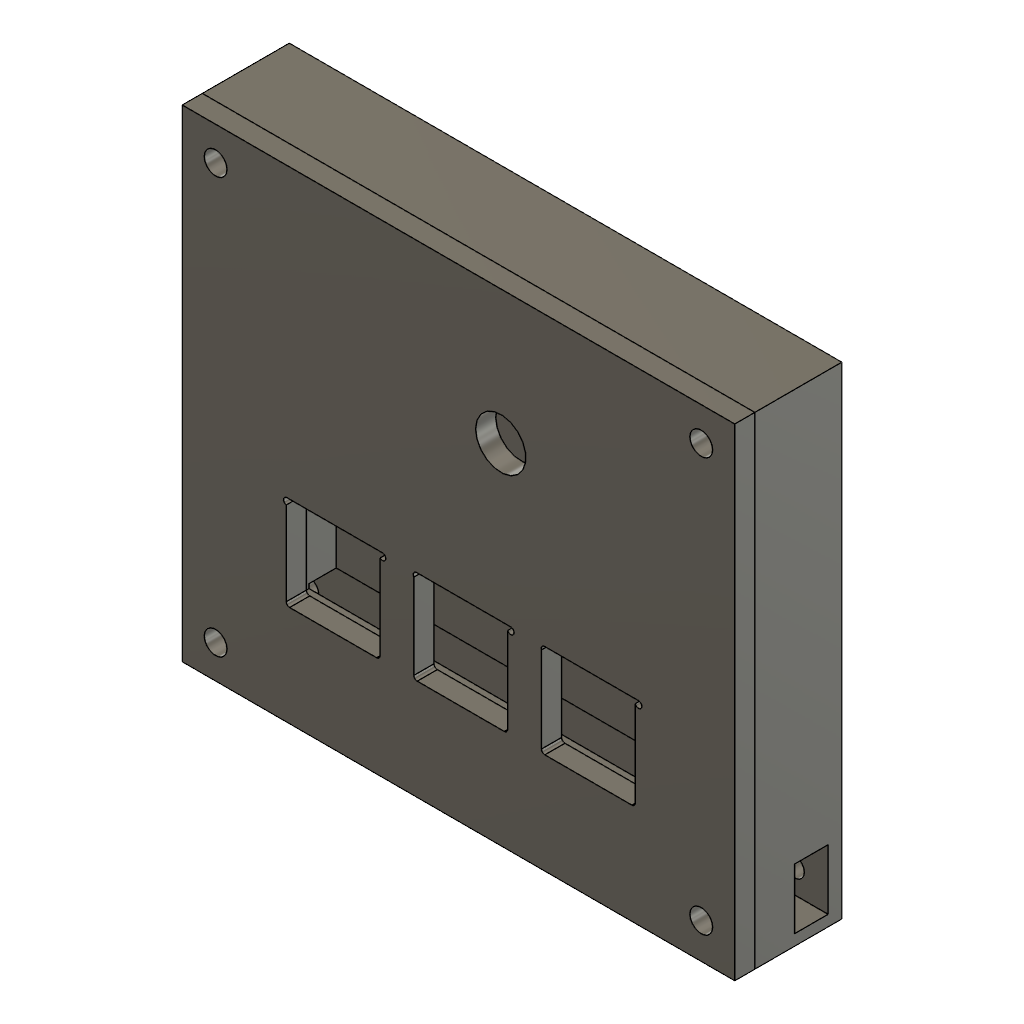
Macropad_Case_Assembly (Autodesk Fusion 360 design; units mm, degrees)
part number: 2026-10-26-13-07-27-418
Autodesk Fusion 360 part; units mm, degrees
sketch "Sketch1" plane through (0, 0, 0) normal (0, 0, 1) x (1, 0, 0)
  line L0 (0, 0) -> (62.5, 0)
  line L1 (62.5, 0) -> (62.5, 52)
  line L2 (62.5, 52) -> (0, 52)
  line L3 (0, 52) -> (0, 0)
  line L4 (-10, 62) -> (72.5, 62)
  line L5 (72.5, 62) -> (72.5, -10)
  line L6 (72.5, -10) -> (-10, -10)
  line L7 (-10, -10) -> (-10, 62)
  circle A0 centre (-5, 57) radius 1.45
  circle A1 centre (-5, -5) radius 1.45
  circle A2 centre (67.5, -4.7104) radius 1.45
  circle A3 centre (67.5, 57) radius 1.45
  dimension "d1" = 62.5
  dimension "d2" = 52
  dimension "d3" = 82.5
  dimension "d4" = 72
  dimension "d5" = 2.9
  dimension "d6" = 2.9
  dimension "d7" = 2.9
  dimension "d8" = 5
  dimension "d9" = 2.9
  dimension "d10" = 5
  dimension "d11" = 5
  dimension "d12" = 5
  dimension "d24" = 10
  dimension "d25" = 10
  constraint horizontal L0
  constraint vertical L1
  constraint horizontal L2
  constraint vertical L3
  constraint coincident L0.start L3.end
  constraint horizontal L4
  constraint vertical L5
  constraint horizontal L6
  constraint vertical L7
  measures "d1" distance of L1.end L2.end
  measures "d2" distance of L0.end L1.end
  measures "d3" distance of L4.start L4.end
  measures "d4" distance of L4.start L6.end
  measures "d5" diameter of A0
  measures "d6" diameter of A1
  measures "d7" diameter of A2
  measures "d8" horizontal distance of L0.end A2.centre
  measures "d9" diameter of A3
  measures "d10" horizontal distance of L1.end A3.centre
  measures "d11" vertical distance of L1.end A3.centre
  measures "d12" vertical distance of L2.end A0.centre
  measures "d24" distance of L3 L7
  measures "d25" distance of L2 L4
extrude "Extrude1" add sketch "Sketch1" along normal blind 3 contours L0 L1 L2 L3 | L4 L5 L6 L7 makes body 1
sketch "Sketch2" plane through (0, 0, 3) normal (0, 0, 1) x (1, 0, 0)
  circle A0 centre (-5, -5) radius 1.45
  circle A1 centre (67.5, -4.7104) radius 1.45
  circle A2 centre (-5, 57) radius 1.45
  circle A3 centre (67.5, 57) radius 1.45
  line L0 (-10, -10) -> (72.5, -10)
  line L1 (72.5, -10) -> (72.5, 62)
  line L2 (72.5, 62) -> (-10, 62)
  line L3 (-10, 62) -> (-10, -10)
extrude "Extrude2" add sketch "Sketch1" along normal blind 10 from surface at 3 bodies 1
sketch "plate-2026-10-26T09_43_40.097Z" plane through (0, 0, 13) normal (0, 0, 1) x (1, 0, 0)
  line L0 (5.6967, 15.8929) -> (19.9048, 15.8929)
  line L1 (6.045, 1.8929) -> (19.045, 1.8929)
  line L2 (5.545, 14.9051) -> (5.545, 2.3929)
  line L3 (19.545, 15.0457) -> (19.545, 2.3929)
  arc A0 (5.6967, 15.8929) -> (5.545, 14.9051) centre (5.639, 15.3962) ccw
  arc A1 (19.545, 15.0457) -> (19.9048, 15.8929) centre (19.9048, 15.3929) ccw
  arc A2 (5.545, 2.3929) -> (6.045, 1.8929) centre (6.045, 2.3929) ccw
  arc A3 (19.045, 1.8929) -> (19.545, 2.3929) centre (19.045, 2.3929) ccw
  line L4 (25.0319, 15.8929) -> (39.0527, 15.8929)
  line L5 (25.095, 1.8929) -> (38.095, 1.8929)
  line L6 (24.595, 15.1069) -> (24.595, 2.3929)
  line L7 (38.595, 15.1917) -> (38.595, 2.3929)
  arc A4 (25.0319, 15.8929) -> (24.595, 15.1069) centre (25.0046, 15.3936) ccw
  arc A5 (38.595, 15.1917) -> (39.0527, 15.8929) centre (39.0527, 15.3929) ccw
  arc A6 (24.595, 2.3929) -> (25.095, 1.8929) centre (25.095, 2.3929) ccw
  arc A7 (38.095, 1.8929) -> (38.595, 2.3929) centre (38.095, 2.3929) ccw
  line L8 (44.1245, 15.8929) -> (58.1259, 15.8929)
  line L9 (44.145, 1.8929) -> (57.145, 1.8929)
  line L10 (43.645, 15.2175) -> (43.645, 2.3929)
  line L11 (57.645, 15.256) -> (57.645, 2.3929)
  arc A8 (44.1245, 15.8929) -> (43.645, 15.2175) centre (44.1132, 15.393) ccw
  arc A9 (57.645, 15.256) -> (58.1259, 15.8929) centre (58.1259, 15.3929) ccw
  arc A10 (43.645, 2.3929) -> (44.145, 1.8929) centre (44.145, 2.3929) ccw
  arc A11 (57.145, 1.8929) -> (57.645, 2.3929) centre (57.145, 2.3929) ccw
  line L12 (3.02, -0.6321) -> (60.17, -0.6321)
  line L13 (3.02, 18.7679) -> (60.17, 18.7679)
  line L14 (3.02, -0.6321) -> (3.02, 18.7679)
  line L15 (60.17, -0.6321) -> (60.17, 18.7679)
  dimension "d23" = 19.4
  measures "d23" distance of L12 L13
extrude "Extrude3" [suppressed]
extrude "Extrude4" add sketch "plate-2026-10-26T09_43_40.097Z" along normal blind 3 separate body makes body 2
sketch "Sketch4" plane through (0, 0, 13) normal (0, 0, 1) x (1, 0, 0)
  circle A0 centre (-5, 57) radius 1.45
  circle A1 centre (-5, -5) radius 1.45
  circle A2 centre (67.5, 57) radius 1.45
  line L0 (62.5, 0) -> (0, 0)
  line L1 (0, 0) -> (0, 52)
  line L2 (0, 52) -> (62.5, 52)
  line L3 (62.5, 52) -> (62.5, 0)
  circle A3 centre (67.5, -4.7104) radius 1.45
  line L4 (-10, 62) -> (-10, -10)
  line L5 (-10, -10) -> (72.5, -10)
  line L6 (72.5, -10) -> (72.5, 62)
  line L7 (72.5, 62) -> (-10, 62)
  line L8 (22.8129, -3.3555) -> (32.8129, -3.3555)
  line L9 (32.8129, -3.3555) -> (32.8129, -7.3555)
  line L10 (32.8129, -7.3555) -> (22.8129, -7.3555)
  line L11 (22.8129, -7.3555) -> (22.8129, -3.3555)
  dimension "d21" = 10
  dimension "d22" = 4
  constraint horizontal L8
  constraint vertical L9
  constraint horizontal L10
  constraint vertical L11
  measures "d21" distance of L8.start L8.end
  measures "d22" distance of L8.start L10.end
move_body "Move1" bodies 2 to x (1, 0, 0) y (0, 1, 0) z (0, 0, 1) at (0, 3.152, 0)
sketch "Sketch5" plane through (0, 0, 16) normal (0, 0, 1) x (1, 0, 0)
  arc A0 (44.1245, 19.0449) -> (43.645, 18.3695) centre (44.1132, 18.545) ccw
  line L0 (44.1245, 19.0449) -> (58.1259, 19.0449)
  arc A1 (57.645, 18.408) -> (58.1259, 19.0449) centre (58.1259, 18.5449) ccw
  line L1 (57.645, 18.408) -> (57.645, 5.5449)
  arc A2 (57.145, 5.0449) -> (57.645, 5.5449) centre (57.145, 5.5449) ccw
  line L2 (57.145, 5.0449) -> (44.145, 5.0449)
  arc A3 (43.645, 5.5449) -> (44.145, 5.0449) centre (44.145, 5.5449) ccw
  line L3 (43.645, 5.5449) -> (43.645, 18.3695)
  arc A4 (5.6967, 19.0449) -> (5.545, 18.0571) centre (5.639, 18.5482) ccw
  line L4 (5.6967, 19.0449) -> (19.9048, 19.0449)
  arc A5 (19.545, 18.1977) -> (19.9048, 19.0449) centre (19.9048, 18.5449) ccw
  line L5 (19.545, 18.1977) -> (19.545, 5.5449)
  arc A6 (19.045, 5.0449) -> (19.545, 5.5449) centre (19.045, 5.5449) ccw
  line L6 (19.045, 5.0449) -> (6.045, 5.0449)
  arc A7 (5.545, 5.5449) -> (6.045, 5.0449) centre (6.045, 5.5449) ccw
  line L7 (5.545, 5.5449) -> (5.545, 18.0571)
  arc A8 (25.0319, 19.0449) -> (24.595, 18.2589) centre (25.0046, 18.5456) ccw
  line L8 (25.0319, 19.0449) -> (39.0527, 19.0449)
  arc A9 (38.595, 18.3437) -> (39.0527, 19.0449) centre (39.0527, 18.5449) ccw
  line L9 (38.595, 18.3437) -> (38.595, 5.5449)
  arc A10 (38.095, 5.0449) -> (38.595, 5.5449) centre (38.095, 5.5449) ccw
  line L10 (38.095, 5.0449) -> (25.095, 5.0449)
  arc A11 (24.595, 5.5449) -> (25.095, 5.0449) centre (25.095, 5.5449) ccw
  line L11 (24.595, 5.5449) -> (24.595, 18.2589)
  line L12 (3.02, 2.5199) -> (60.17, 2.5199)
  line L13 (60.17, 2.5199) -> (60.17, 21.9199)
  line L14 (60.17, 21.9199) -> (3.02, 21.9199)
  line L15 (3.02, 21.9199) -> (3.02, 2.5199)
extrude "Extrude5" [suppressed]
sketch "Sketch6" plane through (0, 0, 16) normal (0, 0, 1) x (1, 0, 0)
  arc A0 (44.1245, 19.0449) -> (43.645, 18.3695) centre (44.1132, 18.545) ccw
  line L0 (44.1245, 19.0449) -> (58.1259, 19.0449)
  arc A1 (57.645, 18.408) -> (58.1259, 19.0449) centre (58.1259, 18.5449) ccw
  line L1 (57.645, 18.408) -> (57.645, 5.5449)
  arc A2 (57.145, 5.0449) -> (57.645, 5.5449) centre (57.145, 5.5449) ccw
  line L2 (57.145, 5.0449) -> (44.145, 5.0449)
  arc A3 (43.645, 5.5449) -> (44.145, 5.0449) centre (44.145, 5.5449) ccw
  line L3 (43.645, 5.5449) -> (43.645, 18.3695)
  arc A4 (5.6967, 19.0449) -> (5.545, 18.0571) centre (5.639, 18.5482) ccw
  line L4 (5.6967, 19.0449) -> (19.9048, 19.0449)
  arc A5 (19.545, 18.1977) -> (19.9048, 19.0449) centre (19.9048, 18.5449) ccw
  line L5 (19.545, 18.1977) -> (19.545, 5.5449)
  arc A6 (19.045, 5.0449) -> (19.545, 5.5449) centre (19.045, 5.5449) ccw
  line L6 (19.045, 5.0449) -> (6.045, 5.0449)
  arc A7 (5.545, 5.5449) -> (6.045, 5.0449) centre (6.045, 5.5449) ccw
  line L7 (5.545, 5.5449) -> (5.545, 18.0571)
  arc A8 (25.0319, 19.0449) -> (24.595, 18.2589) centre (25.0046, 18.5456) ccw
  line L8 (25.0319, 19.0449) -> (39.0527, 19.0449)
  arc A9 (38.595, 18.3437) -> (39.0527, 19.0449) centre (39.0527, 18.5449) ccw
  line L9 (38.595, 18.3437) -> (38.595, 5.5449)
  arc A10 (38.095, 5.0449) -> (38.595, 5.5449) centre (38.095, 5.5449) ccw
  line L10 (38.095, 5.0449) -> (25.095, 5.0449)
  arc A11 (24.595, 5.5449) -> (25.095, 5.0449) centre (25.095, 5.5449) ccw
  line L11 (24.595, 5.5449) -> (24.595, 18.2589)
  line L12 (3.02, 2.5199) -> (60.17, 2.5199)
  line L13 (60.17, 2.5199) -> (60.17, 21.9199)
  line L14 (60.17, 21.9199) -> (3.02, 21.9199)
  line L15 (3.02, 21.9199) -> (3.02, 2.5199)
  line L16 (72.5, 62) -> (-10, 62)
  line L17 (-10, 62) -> (-10, -10)
  line L18 (72.5, -10) -> (72.5, 62)
  line L19 (-10, -10) -> (72.5, -10)
extrude "Extrude6" add sketch "Sketch6" against normal blind 3 contours L16 L17 L18 L19 bodies 2
sketch "Sketch7" plane through (0, 0, 16) normal (0, 0, 1) x (1, 0, 0)
  line L0 (-10, -10) -> (72.5, -10)
  line L1 (72.5, -10) -> (72.5, 62)
  line L2 (72.5, 62) -> (-10, 62)
  line L3 (-10, 62) -> (-10, -10)
  arc A0 (44.1245, 19.0449) -> (43.645, 18.3695) centre (44.1132, 18.545) ccw
  line L4 (44.1245, 19.0449) -> (58.1259, 19.0449)
  arc A1 (57.645, 18.408) -> (58.1259, 19.0449) centre (58.1259, 18.5449) ccw
  line L5 (57.645, 18.408) -> (57.645, 5.5449)
  arc A2 (57.145, 5.0449) -> (57.645, 5.5449) centre (57.145, 5.5449) ccw
  line L6 (57.145, 5.0449) -> (44.145, 5.0449)
  arc A3 (43.645, 5.5449) -> (44.145, 5.0449) centre (44.145, 5.5449) ccw
  line L7 (43.645, 5.5449) -> (43.645, 18.3695)
  arc A4 (5.6967, 19.0449) -> (5.545, 18.0571) centre (5.639, 18.5482) ccw
  line L8 (5.6967, 19.0449) -> (19.9048, 19.0449)
  arc A5 (19.545, 18.1977) -> (19.9048, 19.0449) centre (19.9048, 18.5449) ccw
  line L9 (19.545, 18.1977) -> (19.545, 5.5449)
  arc A6 (19.045, 5.0449) -> (19.545, 5.5449) centre (19.045, 5.5449) ccw
  line L10 (19.045, 5.0449) -> (6.045, 5.0449)
  arc A7 (5.545, 5.5449) -> (6.045, 5.0449) centre (6.045, 5.5449) ccw
  line L11 (5.545, 5.5449) -> (5.545, 18.0571)
  arc A8 (25.0319, 19.0449) -> (24.595, 18.2589) centre (25.0046, 18.5456) ccw
  line L12 (25.0319, 19.0449) -> (39.0527, 19.0449)
  arc A9 (38.595, 18.3437) -> (39.0527, 19.0449) centre (39.0527, 18.5449) ccw
  line L13 (38.595, 18.3437) -> (38.595, 5.5449)
  arc A10 (38.095, 5.0449) -> (38.595, 5.5449) centre (38.095, 5.5449) ccw
  line L14 (38.095, 5.0449) -> (25.095, 5.0449)
  arc A11 (24.595, 5.5449) -> (25.095, 5.0449) centre (25.095, 5.5449) ccw
  line L15 (24.595, 5.5449) -> (24.595, 18.2589)
  circle A12 centre (37.565, 42.025) radius 3.75
  point P0 (37.565, 42.025)
  dimension "d29" = 47.565
  dimension "d30" = 52.025
  dimension "d31" = 7.5
  constraint coincident P0 A12.centre
  measures "d29" distance of L3 P0
  measures "d30" distance of L0 P0
  measures "d31" diameter of A12
extrude "Extrude7" cut sketch "Sketch7" against normal blind 3 contours A12 bodies 2
sketch "Sketch8" plane through (0, 0, 16) normal (0, 0, 1) x (1, 0, 0)
  circle A0 centre (37.565, 42.025) radius 3.75
  line L0 (-10, -10) -> (72.5, -10)
  line L1 (72.5, -10) -> (72.5, 62)
  line L2 (72.5, 62) -> (-10, 62)
  line L3 (-10, 62) -> (-10, -10)
  arc A1 (44.1245, 19.0449) -> (43.645, 18.3695) centre (44.1132, 18.545) ccw
  line L4 (44.1245, 19.0449) -> (58.1259, 19.0449)
  arc A2 (57.645, 18.408) -> (58.1259, 19.0449) centre (58.1259, 18.5449) ccw
  line L5 (57.645, 18.408) -> (57.645, 5.5449)
  arc A3 (57.145, 5.0449) -> (57.645, 5.5449) centre (57.145, 5.5449) ccw
  line L6 (57.145, 5.0449) -> (44.145, 5.0449)
  arc A4 (43.645, 5.5449) -> (44.145, 5.0449) centre (44.145, 5.5449) ccw
  line L7 (43.645, 5.5449) -> (43.645, 18.3695)
  arc A5 (5.6967, 19.0449) -> (5.545, 18.0571) centre (5.639, 18.5482) ccw
  line L8 (5.6967, 19.0449) -> (19.9048, 19.0449)
  arc A6 (19.545, 18.1977) -> (19.9048, 19.0449) centre (19.9048, 18.5449) ccw
  line L9 (19.545, 18.1977) -> (19.545, 5.5449)
  arc A7 (19.045, 5.0449) -> (19.545, 5.5449) centre (19.045, 5.5449) ccw
  line L10 (19.045, 5.0449) -> (6.045, 5.0449)
  arc A8 (5.545, 5.5449) -> (6.045, 5.0449) centre (6.045, 5.5449) ccw
  line L11 (5.545, 5.5449) -> (5.545, 18.0571)
  arc A9 (25.0319, 19.0449) -> (24.595, 18.2589) centre (25.0046, 18.5456) ccw
  line L12 (25.0319, 19.0449) -> (39.0527, 19.0449)
  arc A10 (38.595, 18.3437) -> (39.0527, 19.0449) centre (39.0527, 18.5449) ccw
  line L13 (38.595, 18.3437) -> (38.595, 5.5449)
  arc A11 (38.095, 5.0449) -> (38.595, 5.5449) centre (38.095, 5.5449) ccw
  line L14 (38.095, 5.0449) -> (25.095, 5.0449)
  arc A12 (24.595, 5.5449) -> (25.095, 5.0449) centre (25.095, 5.5449) ccw
  line L15 (24.595, 5.5449) -> (24.595, 18.2589)
  circle A13 centre (67.5, -4.7104) radius 1.45
  circle A14 centre (-5, -5) radius 1.45
  circle A15 centre (-5, 57) radius 1.45
  circle A16 centre (67.5, 57) radius 1.45
  circle A17 centre (-5, -5) radius 1.7
  circle A18 centre (-5, 57) radius 1.7
  circle A19 centre (67.5, 57) radius 1.7
  circle A20 centre (67.5, -4.7104) radius 1.7
  dimension "d34" = 3.4
  dimension "d35" = 3.4
  dimension "d36" = 3.4
  dimension "d37" = 3.4
  constraint concentric A14 A17
  constraint concentric A15 A18
  constraint concentric A16 A19
  constraint concentric A13 A20
  measures "d34" diameter of A17
  measures "d35" diameter of A18
  measures "d36" diameter of A19
  measures "d37" diameter of A20
extrude "Extrude8" cut sketch "Sketch8" against normal blind 3 contours A13 | A14 | A15 | A16 | A17 | A18 | A19 | A20 bodies 2
sketch "Sketch9" plane through (0, 0, 13) normal (0, 0, 1) x (1, 0, 0)
  circle A0 centre (67.5, 57) radius 1.45
  circle A1 centre (-5, 57) radius 1.45
  circle A2 centre (67.5, -4.7104) radius 1.45
  line L0 (62.5, 0) -> (0, 0)
  line L1 (0, 0) -> (0, 52)
  line L2 (0, 52) -> (62.5, 52)
  line L3 (62.5, 52) -> (62.5, 0)
  circle A3 centre (-5, -5) radius 1.45
  line L4 (-10, 62) -> (-10, -10)
  line L5 (-10, -10) -> (72.5, -10)
  line L6 (72.5, -10) -> (72.5, 62)
  line L7 (72.5, 62) -> (-10, 62)
  circle A4 centre (67.5, 57) radius 1.45
  circle A5 centre (67.5, -4.7104) radius 1.45
  circle A6 centre (-5, -5) radius 1.45
  circle A7 centre (-5, 57) radius 1.45
  circle A8 centre (-5, -5) radius 2.35
  circle A9 centre (67.5, -4.7104) radius 2.35
  circle A10 centre (67.5, 57) radius 2.35
  circle A11 centre (-5, 57) radius 2.35
  dimension "d40" = 4.7
  dimension "d41" = 4.7
  dimension "d42" = 4.7
  dimension "d43" = 4.7
  constraint concentric A6 A8
  constraint concentric A5 A9
  constraint concentric A4 A10
  constraint concentric A7 A11
  measures "d40" diameter of A8
  measures "d41" diameter of A9
  measures "d42" diameter of A10
  measures "d43" diameter of A11
extrude "Extrude9" cut sketch "Sketch9" against normal blind 5 contours A8 | A9 | A10 | A11 bodies 1
sketch "Sketch10" plane through (-10, 0, 0) normal (-1, 0, 0) x (0, 0, 1)
  line L0 (0, 62) -> (0, -10)
  line L1 (0, -10) -> (13, -10)
  line L2 (13, -10) -> (13, 62)
  line L3 (13, 62) -> (0, 62)
  line L4 (2.0608, 0.6369) -> (7.0608, 0.6369)
  line L5 (7.0608, 0.6369) -> (7.0608, -8.3631)
  line L6 (7.0608, -8.3631) -> (2.0608, -8.3631)
  line L7 (2.0608, -8.3631) -> (2.0608, 0.6369)
  dimension "d48" = 5
  dimension "d49" = 9
  constraint horizontal L4
  constraint vertical L5
  constraint horizontal L6
  constraint vertical L7
  measures "d48" distance of L5 L7
  measures "d49" distance of L4 L6
extrude "Extrude10" cut sketch "Sketch10" against normal through all contours L4 L5 L6 L7 bodies 1
sketch "Sketch11" plane through (0, 0, 0) normal (0, 0, 1) x (1, 0, 0)
move_face "OffsetFaces1" offset -0.7 1 faces at (62.5, 34.879, 7.6869) on bodies 1
